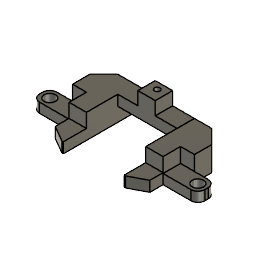
Final Final Assembly (Autodesk Fusion 360 archive; units mm, degrees)
design "Static Arm"
Autodesk Fusion 360 part; units mm, degrees
(part 1 of 3)
sketch "Sketch1" plane through (0, 0, 0) normal (0, 0, 1) x (1, 0, 0)
  line L0 (2.54, 0) -> (57.7596, 0)
  line L1 (60.2996, 2.54) -> (60.2996, 3.81)
  line L2 (57.7596, 6.35) -> (2.54, 6.35)
  line L3 (0, 3.81) -> (0, 2.54)
  circle A0 centre (3.175, 3.175) radius 2.0955
  circle A1 centre (57.1246, 3.175) radius 2.0955
  arc A2 (60.2996, 3.81) -> (57.7596, 6.35) centre (57.7596, 3.81) ccw
  arc A3 (57.7596, 0) -> (60.2996, 2.54) centre (57.7596, 2.54) ccw
  arc A4 (2.54, 6.35) -> (0, 3.81) centre (2.54, 3.81) ccw
  arc A5 (0, 2.54) -> (2.54, 0) centre (2.54, 2.54) ccw
  line L4 (13.335, 17.78) -> (41.275, 17.78)
  line L5 (41.275, 17.78) -> (41.275, 11.43)
  line L6 (41.275, 11.43) -> (13.335, 11.43)
  line L7 (13.335, 11.43) -> (13.335, 17.78)
  line L8 (13.335, 17.78) -> (19.685, 17.78)
  line L9 (19.685, 17.78) -> (19.685, 0)
  line L10 (19.685, 0) -> (13.335, 0)
  line L11 (13.335, 0) -> (13.335, 17.78)
  line L12 (47.5996, 17.78) -> (41.2496, 17.78)
  line L13 (41.2496, 17.78) -> (41.2496, 0)
  line L14 (41.2496, 0) -> (47.5996, 0)
  line L15 (47.5996, 0) -> (47.5996, 17.78)
  line L16 (13.335, 17.78) -> (8.255, 17.78)
  line L17 (8.255, 17.78) -> (8.255, 0)
  line L18 (8.255, 0) -> (13.335, 0)
  line L19 (13.335, 0) -> (13.335, 17.78)
  line L20 (13.335, 17.78) -> (8.255, 12.7)
  line L21 (47.5996, 17.78) -> (52.6796, 17.78)
  line L22 (52.6796, 17.78) -> (52.6796, 0)
  line L23 (52.6796, 0) -> (47.5996, 0)
  line L24 (47.5996, 0) -> (47.5996, 17.78)
  line L25 (47.5996, 17.78) -> (52.6796, 12.7)
  point P0 (60.2996, 0)
  dimension "d1" = 6.35
  dimension "d2" = 60.2996
  dimension "d3" = 4.191
  dimension "d4" = 4.191
  dimension "d5" = 53.9496
  dimension "d6" = 3.175
  dimension "d7" = 3.175
  dimension "d8" = 2.54
  dimension "d9" = 2.54
  dimension "d10" = 2.54
  dimension "d11" = 2.54
  dimension "d14" = 6.35
  dimension "d15" = 10.16
  dimension "d17" = 6.35
  dimension "d18" = 10.16
  dimension "d19" = 5.08
  dimension "d20" = 6.35
  dimension "d39" = 27.94
  dimension "d80" = 5.08
  dimension "d81" = 45
  dimension "d82" = 5.08
  dimension "d83" = 45
  constraint horizontal L0
  constraint vertical L1
  constraint horizontal L2
  constraint vertical L3
  constraint horizontal A0.centre A1.centre
  constraint tangent L2 A2
  constraint tangent L1 A2
  constraint coincident P0 L0
  constraint coincident P0 L1
  constraint tangent L0 A3
  constraint tangent L1 A3
  constraint tangent L3 A4
  constraint tangent L2 A4
  constraint coincident origin L3
  constraint coincident origin L0
  constraint tangent L3 A5
  constraint tangent L0 A5
  constraint horizontal L4
  constraint vertical L5
  constraint horizontal L6
  constraint vertical L7
  constraint horizontal L8
  constraint vertical L9
  constraint horizontal L10
  constraint vertical L11
  constraint coincident L0 L9.end
  constraint horizontal L12
  constraint vertical L13
  constraint horizontal L14
  constraint vertical L15
  constraint coincident L0 L13.end
  constraint coincident L4 L12.start
  constraint horizontal L16
  constraint vertical L17
  constraint horizontal L18
  constraint vertical L19
  constraint coincident L0 L17.end
  constraint coincident L17 L20.end
  constraint horizontal L21
  constraint vertical L22
  constraint horizontal L23
  constraint vertical L24
  constraint coincident L0 L22.end
  constraint coincident L22 L25.end
  measures "d1" distance of L0 L2
  measures "d2" distance of origin P0
  measures "d3" diameter of A0
  measures "d4" diameter of A1
  measures "d5" distance of A0.centre A1.centre
  measures "d6" distance of L3 A0.centre
  measures "d7" vertical distance of origin A0.centre
  measures "d8" radius of A2
  measures "d9" radius of A3
  measures "d10" radius of A4
  measures "d11" radius of A5
  measures "d14" distance of L4 L6
  measures "d15" distance of A0.centre L11
  measures "d17" distance of L13 L15
  measures "d18" distance of A3.centre L15
  measures "d19" distance of L2 L6
  measures "d20" distance of L9 L11
  measures "d39" distance of L4.start L4.end
  measures "d80" distance of L4.start L16.end
  measures "d81" angle of L16 L20
  measures "d82" distance of L12.start L21.end
  measures "d83" angle of L21 L25
extrude "Extrude1" add sketch "Sketch1" along normal blind 3.81 contours L0 L2 L3 A4 A5 L17 | L0 L2 L11 L17 L18 L19 | L0 L2 L9 L10 L11 L19 | L2 L7 L11 L17 L19 L20 | L2 L6 L9 L11 L19 | L0 L2 L13 L14 L15 L24 | L4 L6 L7 L8 L9 L11 L19 | L0 L2 L15 L22 L23 L24 | L2 L5 L6 L12 L13 L15 L24 | L4 L6 L9 L13 | L0 L1 L2 A2 A3 L22 | L2 L15 L22 L24 L25 makes body 1
sketch "Sketch5" plane through (0, 0, 3.81) normal (0, 0, -1) x (1, 0, 0)
  circle A0 centre (63.4746, -3.175) radius 2.0955
  circle A1 centre (3.175, -3.175) radius 2.0955
  line L0 (47.5996, 0) -> (47.5996, -11.43)
  line L1 (47.5996, -11.43) -> (19.335, -11.43)
  line L2 (19.335, -11.43) -> (19.335, 0)
  line L3 (19.335, 0) -> (2.54, 0)
  arc A2 (2.54, 0) -> (0, -2.54) centre (2.54, -2.54) ccw
  line L4 (0, -2.54) -> (0, -3.81)
  arc A3 (0, -3.81) -> (2.54, -6.35) centre (2.54, -3.81) ccw
  line L5 (2.54, -6.35) -> (13.335, -6.35)
  line L6 (13.335, -6.35) -> (13.335, -17.78)
  line L7 (13.335, -17.78) -> (53.9496, -17.78)
  line L8 (53.9496, -17.78) -> (53.9496, -6.35)
  line L9 (53.9496, -6.35) -> (64.1096, -6.35)
  arc A4 (64.1096, -6.35) -> (66.6496, -3.81) centre (64.1096, -3.81) ccw
  line L10 (66.6496, -3.81) -> (66.6496, -2.54)
  arc A5 (66.6496, -2.54) -> (64.1096, 0) centre (64.1096, -2.54) ccw
  line L11 (64.1096, 0) -> (47.5996, 0)
  line L12 (26.9748, -11.43) -> (33.3248, -11.43)
  line L13 (33.3248, -11.43) -> (33.3248, -17.78)
  line L14 (33.3248, -17.78) -> (26.9748, -17.78)
  line L15 (26.9748, -17.78) -> (26.9748, -11.43)
  circle A6 centre (3.175, -3.175) radius 2.0955
  line L16 (8.255, -6.35) -> (2.54, -6.35)
  arc A7 (0, -3.81) -> (2.54, -6.35) centre (2.54, -3.81) ccw
  line L17 (0, -3.81) -> (0, -2.54)
  arc A8 (2.54, 0) -> (0, -2.54) centre (2.54, -2.54) ccw
  line L18 (2.54, 0) -> (19.685, 0)
  line L19 (19.685, 0) -> (19.685, -11.43)
  line L20 (19.685, -11.43) -> (41.2496, -11.43)
  line L21 (41.2496, -11.43) -> (41.2496, -17.78)
  line L22 (41.2496, -17.78) -> (13.335, -17.78)
  line L23 (13.335, -17.78) -> (8.255, -12.7)
  line L24 (8.255, -12.7) -> (8.255, -6.35)
  dimension "d35" = 6.35
  dimension "d36" = 26.9748
  constraint horizontal L12
  constraint vertical L13
  constraint horizontal L14
  constraint vertical L15
  constraint coincident L7 L13.end
  constraint coincident L1 L12.start
  measures "d35" distance of L13 L15
  measures "d36" distance of origin L15
extrude "Extrude4" add sketch "Sketch5" against normal blind 4.8006 contours L1 L7 L12 L13 L14 L15 L20 L22 bodies 1
sketch "Sketch2" plane through (0, 0, 8.6106) normal (0, 0, -1) x (1, 0, 0)
  circle A0 centre (63.4746, -3.175) radius 2.0955
  circle A1 centre (3.175, -3.175) radius 2.0955
  line L0 (47.5996, 0) -> (47.5996, -11.43)
  line L1 (47.5996, -11.43) -> (36.4998, -11.43)
  line L2 (19.335, -11.43) -> (19.335, 0)
  line L3 (19.335, 0) -> (2.54, 0)
  arc A2 (2.54, 0) -> (0, -2.54) centre (2.54, -2.54) ccw
  line L4 (0, -2.54) -> (0, -3.81)
  arc A3 (0, -3.81) -> (2.54, -6.35) centre (2.54, -3.81) ccw
  line L5 (2.54, -6.35) -> (13.335, -6.35)
  line L6 (13.335, -6.35) -> (13.335, -17.78)
  line L7 (36.4998, -17.78) -> (53.9496, -17.78)
  line L8 (53.9496, -17.78) -> (53.9496, -6.35)
  line L9 (53.9496, -6.35) -> (64.1096, -6.35)
  arc A4 (64.1096, -6.35) -> (66.6496, -3.81) centre (64.1096, -3.81) ccw
  line L10 (66.6496, -3.81) -> (66.6496, -2.54)
  arc A5 (66.6496, -2.54) -> (64.1096, 0) centre (64.1096, -2.54) ccw
  line L11 (64.1096, 0) -> (47.5996, 0)
  circle A6 centre (30.1498, -15.3416) radius 1
  line L12 (36.4998, -11.43) -> (36.4998, -17.78)
  line L13 (30.1498, -17.78) -> (30.1498, -11.43)
  line L14 (30.1498, -11.43) -> (19.335, -11.43)
  line L15 (13.335, -17.78) -> (30.1498, -17.78)
  line L16 (30.1498, -17.78) -> (36.4998, -17.78)
  line L17 (36.4998, -17.78) -> (36.4998, -11.43)
  line L18 (36.4998, -11.43) -> (30.1498, -11.43)
  line L19 (30.1498, -11.43) -> (30.1498, -17.78)
  circle A7 centre (63.4746, -3.175) radius 2.0955
  circle A8 centre (3.175, -3.175) radius 2.0955
  line L20 (47.5996, -11.43) -> (47.5996, 0)
  line L21 (2.54, 0) -> (19.335, 0)
  arc A9 (66.6496, -2.54) -> (64.1096, 0) centre (64.1096, -2.54) ccw
  line L22 (66.6496, -2.54) -> (66.6496, -3.81)
  arc A10 (64.1096, -6.35) -> (66.6496, -3.81) centre (64.1096, -3.81) ccw
  line L23 (13.335, -6.35) -> (2.54, -6.35)
  line L24 (53.9496, -6.35) -> (53.9496, -17.78)
  line L25 (30.1498, -17.78) -> (13.335, -17.78)
  line L26 (13.335, -17.78) -> (13.335, -6.35)
  arc A11 (0, -3.81) -> (2.54, -6.35) centre (2.54, -3.81) ccw
  line L27 (0, -3.81) -> (0, -2.54)
  arc A12 (2.54, 0) -> (0, -2.54) centre (2.54, -2.54) ccw
  line L28 (19.335, 0) -> (19.335, -11.43)
  line L29 (19.335, -11.43) -> (30.1498, -11.43)
  line L30 (30.1498, -11.43) -> (30.1498, -17.78)
  line L31 (36.4998, -17.78) -> (36.4998, -11.43)
  line L32 (36.4998, -11.43) -> (47.5996, -11.43)
  line L33 (47.5996, 0) -> (64.1096, 0)
  line L34 (64.1096, -6.35) -> (53.9496, -6.35)
  line L35 (53.9496, -17.78) -> (36.4998, -17.78)
  line L36 (33.3248, -17.78) -> (26.9748, -17.78)
  line L37 (26.9748, -17.78) -> (26.9748, -11.43)
  line L38 (26.9748, -11.43) -> (33.3248, -11.43)
  line L39 (33.3248, -11.43) -> (33.3248, -17.78)
  dimension "d21" = 2
  dimension "d24" = 3.9116
  dimension "d53" = 30.1498
  measures "d21" diameter of A6
  measures "d24" distance of L1 A6.centre
  measures "d53" distance of L4 A6.centre
extrude "Extrude2" cut sketch "Sketch2" along normal blind 12.7 contours A6 L13 L19 L30 | A6 L13 L19 L30 bodies 1
sketch "Sketch3" plane through (0, 0, 3.81) normal (0, 0, 1) x (-1, 0, 0)
  line L0 (-41.2496, 0) -> (-57.7596, 0)
  line L1 (-57.7596, -6.35) -> (-52.6796, -6.35)
  line L2 (-41.275, -11.43) -> (-41.2496, -11.43)
  circle A0 centre (-16.51, -14.605) radius 2.1
  circle A1 centre (-44.4246, -14.605) radius 2.1
  line L3 (-47.5996, -17.78) -> (-41.275, -17.78)
  line L4 (-41.275, -17.78) -> (-41.275, -11.43)
  line L5 (-41.2496, -11.43) -> (-41.2496, 0)
  arc A2 (-57.7596, 0) -> (-60.2996, -2.54) centre (-57.7596, -2.54) ccw
  line L6 (-60.2996, -2.54) -> (-60.2996, -3.81)
  arc A3 (-60.2996, -3.81) -> (-57.7596, -6.35) centre (-57.7596, -3.81) ccw
  circle A4 centre (-57.1246, -3.175) radius 2.0955
  line L7 (-52.6796, -6.35) -> (-52.6796, -12.7)
  line L8 (-52.6796, -12.7) -> (-47.5996, -17.78)
  dimension "d27" = 4.2
  dimension "d28" = 4.2
  dimension "d40" = 14.605
  dimension "d41" = 16.51
  dimension "d42" = 27.9146
  constraint horizontal A0.centre A1.centre
  measures "d27" diameter of A1
  measures "d28" diameter of A0
  measures "d40" vertical distance of origin A0.centre
  measures "d41" horizontal distance of origin A0.centre
  measures "d42" distance of A0.centre A1.centre
sketch "Sketch6" plane through (0, 0, 0) normal (0, 0, -1) x (1, 0, 0)
  circle A0 centre (57.1246, -3.175) radius 2.0955
  line L0 (52.6796, -6.35) -> (57.7596, -6.35)
  arc A1 (57.7596, -6.35) -> (60.2996, -3.81) centre (57.7596, -3.81) ccw
  line L1 (60.2996, -3.81) -> (60.2996, -2.54)
  arc A2 (60.2996, -2.54) -> (57.7596, 0) centre (57.7596, -2.54) ccw
  line L2 (57.7596, 0) -> (41.2496, 0)
  line L3 (41.2496, 0) -> (41.2496, -11.43)
  line L4 (41.2496, -11.43) -> (41.275, -11.43)
  line L5 (41.275, -11.43) -> (41.275, -17.78)
  line L6 (41.275, -17.78) -> (47.5996, -17.78)
  line L7 (41.2496, 0) -> (47.5996, 0)
  line L8 (47.5996, 0) -> (47.5996, -17.78)
  line L9 (47.5996, -17.78) -> (41.2496, -17.78)
  line L10 (41.2496, -17.78) -> (41.2496, 0)
  line L11 (47.5996, 0) -> (57.7596, 0)
  line L12 (60.2996, -2.54) -> (60.2996, -3.81)
  line L13 (57.7596, -6.35) -> (47.5996, -6.35)
  line L14 (47.5996, -6.35) -> (47.5996, 0)
  arc A3 (60.2996, -2.54) -> (57.7596, 0) centre (57.7596, -2.54) ccw
  arc A4 (57.7596, -6.35) -> (60.2996, -3.81) centre (57.7596, -3.81) ccw
  line L15 (19.685, -17.78) -> (13.335, -17.78)
  line L16 (13.335, -17.78) -> (13.335, 0)
  line L17 (13.335, 0) -> (19.685, 0)
  line L18 (19.685, 0) -> (19.685, -17.78)
  line L19 (13.335, 0) -> (2.54, 0)
  line L20 (0, -2.54) -> (0, -3.81)
  line L21 (2.54, -6.35) -> (13.335, -6.35)
  line L22 (13.335, -6.35) -> (13.335, 0)
  arc A5 (2.54, 0) -> (0, -2.54) centre (2.54, -2.54) ccw
  arc A6 (0, -3.81) -> (2.54, -6.35) centre (2.54, -3.81) ccw
  circle A7 centre (3.175, -3.175) radius 2.0955
  circle A8 centre (16.51, -14.5999) radius 2.0955
  line L23 (47.5996, -17.78) -> (52.6796, -12.7)
  line L24 (52.6796, -12.7) -> (52.6796, -6.35)
  point P0 (19.685, 0)
  point P1 (0, -2.54)
  point P2 (41.2496, -17.78)
  point P3 (13.335, -17.78)
  dimension "d43" = 2.54
  dimension "d44" = 2.54
  dimension "d45" = 10.16
  dimension "d46" = 1.27
  dimension "d54" = 6.35
  dimension "d55" = 2.54
  dimension "d56" = 2.54
  dimension "d57" = 6.35
  dimension "d58" = 3.175
  dimension "d59" = 4.191
  dimension "d60" = 3.175
  dimension "d61" = 4.191
  dimension "d62" = 3.1801
  dimension "d63" = 3.175
  constraint horizontal L7
  constraint vertical L8
  constraint horizontal L9
  constraint vertical L10
  constraint coincident L6.end L8.end
  constraint coincident L2.end L3.start
  constraint horizontal L11
  constraint vertical L12
  constraint horizontal L13
  constraint vertical L14
  constraint tangent L11 A3
  constraint tangent L12 A3
  constraint tangent L12 A4
  constraint tangent L13 A4
  constraint horizontal L15
  constraint vertical L16
  constraint horizontal L17
  constraint vertical L18
  constraint coincident P0 L17.end
  constraint horizontal L19
  constraint vertical L20
  constraint horizontal L21
  constraint vertical L22
  constraint tangent L20 A5
  constraint tangent L19 A5
  constraint tangent L20 A6
  constraint tangent L21 A6
  constraint coincident P1 L20.start
  measures "d43" radius of A3
  measures "d44" radius of A4
  measures "d45" distance of L13.end L0.end
  measures "d46" distance of L1.end A1.end
  measures "d54" distance of L16 L18
  measures "d55" radius of A5
  measures "d56" radius of A6
  measures "d57" distance of L19 L21
  measures "d58" distance of L19 A7.centre
  measures "d59" diameter of A7
  measures "d60" distance of L20 A7.centre
  measures "d61" diameter of A8
  measures "d62" distance of L15 A8.centre
  measures "d63" distance of L16 A8.centre
extrude "Extrude6" cut sketch "Sketch6" against normal blind 7.62 contours L0 A1 L1 A2 L2 L8 L11 L12 L13 L14 A3 A4 | L16 L19 L20 L21 L22 A5 A6 bodies 1
extrude "Extrude5" add sketch "Sketch6" along normal blind 5.08 separate body contours L0 A1 L1 A2 L2 L8 L11 L12 L13 L14 A3 A4 | L2 L3 L4 L5 L6 L7 L8 L9 L10 L14 | L15 L16 L17 L18 L22 | L16 L19 L20 L21 L22 A5 A6 | A8 makes body 2 at (43.3747, 5.9267, 0) makes body 3 at (17.5683, 8.0433, 0)
extrude "Extrude7" cut sketch "Sketch6" along normal blind 1.27 contours L0 A1 L1 A2 L2 L8 L11 L12 L13 L14 A3 A4 | L16 L19 L20 L21 L22 A5 A6 bodies 2
extrude "Extrude8" cut sketch "Sketch6" along normal blind 1.27 contours L16 L19 L20 L21 L22 A5 A6 bodies 3
sketch "Sketch7" plane through (0, 0, 0) normal (0, -1, 0) x (1, 0, 0)
  line L0 (13.335, -1.27) -> (2.54, -1.27)
  line L1 (2.54, -1.27) -> (2.54, -5.08)
  line L2 (2.54, -5.08) -> (19.685, -5.08)
  line L3 (19.685, -5.08) -> (19.685, 0)
  line L4 (19.685, 0) -> (13.335, 0)
  line L5 (13.335, 0) -> (13.335, -1.27)
  line L6 (13.335, -1.27) -> (19.685, -1.27)
  line L7 (19.685, -1.27) -> (19.685, -5.08)
  line L8 (19.685, -5.08) -> (13.335, -5.08)
  line L9 (13.335, -5.08) -> (13.335, -1.27)
  dimension "d66" = 6.35
  constraint horizontal L6
  constraint vertical L7
  constraint horizontal L8
  constraint vertical L9
  constraint coincident L2 L3.start
  constraint coincident L0 L5.end
  constraint coincident L2.end L3.start
  measures "d66" distance of L7 L9
extrude "Extrude9" add sketch "Sketch7" along normal blind 8.4226 contours L2 L3 L6 L7 L8 L9 bodies 3
chamfer "Chamfer1" distance 5.842 angle 30.099 1 edges at (13.335, -8.4226, -3.175) measured on face at (15.4517, -8.4226, -3.81) on bodies 3
sketch "Sketch8" plane through (0, 0, 0) normal (0, -1, 0) x (1, 0, 0)
  line L0 (57.7596, -1.27) -> (47.5996, -1.27)
  line L1 (47.5996, -1.27) -> (47.5996, 0)
  line L2 (47.5996, 0) -> (41.2496, 0)
  line L3 (41.2496, 0) -> (41.2496, -5.08)
  line L4 (41.2496, -5.08) -> (57.7596, -5.08)
  line L5 (57.7596, -5.08) -> (57.7596, -1.27)
  line L6 (41.2496, -5.08) -> (47.5996, -5.08)
  line L7 (47.5996, -5.08) -> (47.5996, -1.27)
  line L8 (47.5996, -1.27) -> (41.2496, -1.27)
  line L9 (41.2496, -1.27) -> (41.2496, -5.08)
  constraint horizontal L6
  constraint vertical L7
  constraint horizontal L8
  constraint vertical L9
  constraint coincident L0.end L1.start
  constraint coincident L3.end L4.start
extrude "Extrude10" add sketch "Sketch8" along normal blind 7.874 contours L3 L4 L6 L7 L8 L9 bodies 2
chamfer "Chamfer2" distance 5.842 angle 27.549 1 edges at (47.5996, -7.874, -3.175) measured on face at (45.4829, -7.874, -3.81) on bodies 2
sketch "Sketch9" plane through (0, 0, 0) normal (0, 0, -1) x (1, 0, 0)
  line L0 (47.5996, -6.35) -> (47.5996, 0)
  line L1 (47.5996, 0) -> (41.2496, 0)
  line L2 (41.2496, 0) -> (41.2496, -11.43)
  line L3 (41.2496, -11.43) -> (41.275, -11.43)
  line L4 (41.275, -11.43) -> (41.275, -17.78)
  line L5 (41.275, -17.78) -> (47.5996, -17.78)
  line L6 (47.5996, -17.78) -> (52.6796, -12.7)
  line L7 (52.6796, -12.7) -> (52.6796, -6.35)
  line L8 (52.6796, -6.35) -> (47.5996, -6.35)
  line L9 (47.5996, -6.35) -> (52.6796, -6.35)
  line L10 (52.6796, -6.35) -> (52.6796, -12.7)
  line L11 (52.6796, -12.7) -> (47.5996, -12.7)
  line L12 (47.5996, -12.7) -> (47.5996, -6.35)
  line L13 (47.5996, -12.7) -> (47.5996, -17.78)
  line L14 (52.6796, -12.7) -> (47.5996, -17.78)
  constraint horizontal L9
  constraint vertical L10
  constraint horizontal L11
  constraint vertical L12
  constraint coincident L6.end L7.start
  constraint coincident L0.start L8.end
  constraint coincident L5.end L6.start
extrude "Extrude11" add sketch "Sketch9" along normal blind 5.08 contours L7 L8 L9 L10 L11 L12 | L6 L11 L13 L14 bodies 1 3 2
sketch "Sketch10" plane through (0, 0, 0) normal (0, 0, -1) x (1, 0, 0)
  line L0 (13.335, 0) -> (13.335, -6.35)
  line L1 (13.335, -6.35) -> (8.255, -6.35)
  line L2 (8.255, -6.35) -> (8.255, -12.7)
  line L3 (8.255, -12.7) -> (13.335, -17.78)
  line L4 (13.335, -17.78) -> (41.2496, -17.78)
  line L5 (41.2496, -17.78) -> (41.2496, -11.43)
  line L6 (41.2496, -11.43) -> (19.685, -11.43)
  line L7 (19.685, -11.43) -> (19.685, 0)
  line L8 (19.685, 0) -> (13.335, 0)
  circle A0 centre (30.1498, -15.3416) radius 1
  line L9 (8.255, -6.35) -> (13.335, -6.35)
  line L10 (13.335, -6.35) -> (13.335, -12.7)
  line L11 (13.335, -12.7) -> (8.255, -12.7)
  line L12 (8.255, -12.7) -> (8.255, -6.35)
  line L13 (13.335, -12.7) -> (13.335, -17.78)
  line L14 (8.255, -12.7) -> (13.335, -17.78)
  dimension "d86" = 5.08
  constraint horizontal L9
  constraint vertical L10
  constraint horizontal L11
  constraint vertical L12
  constraint coincident L1.end L2.start
  constraint coincident L2.end L3.start
  constraint coincident L3.end L4.start
  measures "d86" distance of L10.end L2.end
extrude "Extrude12" add sketch "Sketch10" along normal blind 5.08 contours L1 L2 L9 L10 L11 L12 | L3 L11 L13 L14 bodies 1 3
sketch "Sketch11" plane through (0, 0, -1.27) normal (0, 0, 1) x (-1, 0, 0)
  circle A0 centre (-3.175, -3.175) radius 2.0955
  arc A1 (-2.54, -6.35) -> (0, -3.81) centre (-2.54, -3.81) ccw
  line L0 (0, -3.81) -> (0, -2.54)
  arc A2 (0, -2.54) -> (-2.54, 0) centre (-2.54, -2.54) ccw
  line L1 (-2.54, 0) -> (-13.335, 0)
  line L2 (-13.335, 0) -> (-13.335, -6.35)
  line L3 (-13.335, -6.35) -> (-8.255, -6.35)
  line L4 (-8.255, -6.35) -> (-2.54, -6.35)
  line L5 (-13.335, -6.35) -> (5.715, -6.35)
  line L6 (5.715, -6.35) -> (5.715, 6.35)
  line L7 (5.715, 6.35) -> (-13.335, 6.35)
  line L8 (-13.335, 6.35) -> (-13.335, -6.35)
  line L9 (-47.5996, -6.35) -> (-66.6496, -6.35)
  line L10 (-66.6496, -6.35) -> (-66.6496, 6.35)
  line L11 (-66.6496, 6.35) -> (-47.5996, 6.35)
  line L12 (-47.5996, 6.35) -> (-47.5996, -6.35)
  point P0 (-47.5996, -6.35)
  dimension "d89" = 12.7
  dimension "d90" = 19.05
  dimension "d91" = 12.7
  dimension "d92" = 19.05
  constraint horizontal L5
  constraint vertical L6
  constraint horizontal L7
  constraint vertical L8
  constraint coincident L2.end L3.start
  constraint horizontal L9
  constraint vertical L10
  constraint horizontal L11
  constraint vertical L12
  constraint coincident P0 L9.start
  measures "d89" distance of L9.end L10.end
  measures "d90" distance of P0 L9.end
  measures "d91" distance of L5.end L6.end
  measures "d92" distance of L2.end L5.end
extrude "Extrude13" cut sketch "Sketch11" against normal blind 0.254 bodies 1
fillet "Fillet1" [rolled back] radius 10.16
fillet "Fillet2" [rolled back] radius 10.16
equation "d5 = 2.374 in - 0.25 in"
equation "d36 = ( 2.624 / 2 ) * 1 in - 0.25 in"
equation "d42 = 1.349 in - 0.25 in"
equation "d53 = ( 2.374 / 2 ) * 1 in"

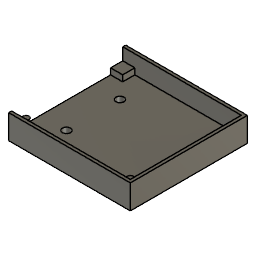
design "Controller Mounting"
Autodesk Fusion 360 part; units mm, degrees
sketch "Sketch1" plane through (0, 0, 0) normal (0, 0, 1) x (1, 0, 0)
  line L0 (0, 0) -> (65.175, 0)
  line L1 (65.175, 0) -> (65.175, 61.175)
  line L2 (65.175, 61.175) -> (0, 61.175)
  line L3 (0, 61.175) -> (0, 0)
  dimension "d1" = 61.175
  dimension "d2" = 65.175
  constraint horizontal L0
  constraint vertical L1
  constraint horizontal L2
  constraint vertical L3
  constraint coincident L0.start L3.end
  measures "d1" distance of L0.start L2.end
  measures "d2" distance of L0.start L0.end
extrude "Extrude1" add sketch "Sketch1" along normal blind 12.7
sketch "Sketch4" plane through (0, 0, 12.7) normal (0, 0, 1) x (-1, 0, 0)
  line L0 (0, -61.175) -> (0, 0)
  line L1 (0, 0) -> (-65.175, 0)
  line L2 (-65.175, 0) -> (-65.175, -61.175)
  line L3 (-65.175, -61.175) -> (0, -61.175)
  line L4 (-1.5875, -1.5875) -> (-63.5875, -1.5875)
  line L5 (-63.5875, -1.5875) -> (-63.5875, -59.5875)
  line L6 (-63.5875, -59.5875) -> (-1.5875, -59.5875)
  line L7 (-1.5875, -59.5875) -> (-1.5875, -1.5875)
  dimension "d10" = 1.5875
  dimension "d11" = 1.5875
  dimension "d12" = 1.5875
  dimension "d13" = 1.5875
  constraint horizontal L4
  constraint vertical L5
  constraint horizontal L6
  constraint vertical L7
  measures "d10" distance of L0 L7
  measures "d11" distance of L3 L6
  measures "d12" distance of L1 L4
  measures "d13" distance of L2 L5
extrude "Extrude2" cut sketch "Sketch4" against normal blind 9.525 contours L4 L5 L6 L7
sketch "Sketch5" plane through (0, 0, 0) normal (-1, 0, 0) x (0, -1, 0)
  line L0 (-61.175, 0) -> (0, 0)
  line L1 (0, 0) -> (0, 12.7)
  line L2 (0, 12.7) -> (-61.175, 12.7)
  line L3 (-61.175, 12.7) -> (-61.175, 0)
  line L4 (-53.2375, 12.7) -> (-7.9375, 12.7)
  line L5 (-7.9375, 12.7) -> (-7.9375, 0)
  line L6 (-53.2375, 0) -> (-53.2375, 12.7)
  line L7 (-53.2375, 3.175) -> (-59.5875, 3.175)
  line L8 (-59.5875, 3.175) -> (-59.5875, 12.7)
  line L9 (-59.5875, 12.7) -> (-53.2375, 12.7)
  line L10 (-53.2375, 12.7) -> (-53.2375, 3.175)
  line L11 (-7.9375, 3.175) -> (-1.5875, 3.175)
  line L12 (-1.5875, 3.175) -> (-1.5875, 12.7)
  line L13 (-1.5875, 12.7) -> (-7.9375, 12.7)
  line L14 (-7.9375, 12.7) -> (-7.9375, 3.175)
  line L15 (-53.2375, 3.175) -> (-7.9375, 3.175)
  dimension "d76" = 1.5875
  dimension "d77" = 3.175
  dimension "d78" = 3.175
  dimension "d79" = 1.5875
  dimension "d80" = 6.35
  dimension "d81" = 6.35
  constraint horizontal L4
  constraint vertical L5
  constraint vertical L6
  constraint coincident L2 L4.start
  constraint horizontal L5.end L6.start
  constraint horizontal L0.end L6.start
  constraint horizontal L7
  constraint vertical L8
  constraint horizontal L9
  constraint vertical L10
  constraint coincident L2 L8.end
  constraint coincident L6 L7.start
  constraint horizontal L11
  constraint vertical L12
  constraint horizontal L13
  constraint vertical L14
  constraint coincident L2 L12.end
  constraint coincident L5 L11.start
  measures "d76" distance of L3 L8
  measures "d77" distance of L0 L7
  measures "d78" distance of L0 L11
  measures "d79" distance of L1 L12
  measures "d80" distance of L8 L10
  measures "d81" distance of L12 L14
extrude "Extrude3" cut sketch "Sketch5" against normal blind 1.5875
sketch "Sketch6" plane through (0, 0, 3.175) normal (0, 0, 1) x (-1, 0, 0)
  circle A0 centre (-59.8375, -5.3375) radius 1.65
  circle A1 centre (-5.3375, -5.3375) radius 1.65
  circle A2 centre (-59.8375, -55.8375) radius 1.65
  circle A3 centre (-5.3375, -55.8375) radius 1.65
  line L0 (-63.5875, -1.5875) -> (-57.2375, -1.5875)
  line L1 (-57.2375, -1.5875) -> (-57.2375, -7.9375)
  line L2 (-57.2375, -7.9375) -> (-63.5875, -7.9375)
  line L3 (-63.5875, -7.9375) -> (-63.5875, -1.5875)
  line L4 (-63.5875, -59.5875) -> (-57.2375, -59.5875)
  line L5 (-57.2375, -59.5875) -> (-57.2375, -53.2375)
  line L6 (-57.2375, -53.2375) -> (-63.5875, -53.2375)
  line L7 (-63.5875, -53.2375) -> (-63.5875, -59.5875)
  line L8 (-1.5875, -59.5875) -> (-7.9375, -59.5875)
  line L9 (-7.9375, -59.5875) -> (-7.9375, -53.2375)
  line L10 (-7.9375, -53.2375) -> (-1.5875, -53.2375)
  line L11 (-1.5875, -53.2375) -> (-1.5875, -59.5875)
  line L12 (-1.5875, -1.5875) -> (-7.9375, -1.5875)
  line L13 (-7.9375, -1.5875) -> (-7.9375, -7.9375)
  line L14 (-7.9375, -7.9375) -> (-1.5875, -7.9375)
  line L15 (-1.5875, -7.9375) -> (-1.5875, -1.5875)
  line L16 (-65.175, 0) -> (-65.175, -61.175)
  line L17 (-65.175, -61.175) -> (0, -61.175)
  line L18 (-1.5875, -1.5875) -> (-63.5875, -1.5875)
  line L19 (-63.5875, -1.5875) -> (-63.5875, -59.5875)
  line L20 (-63.5875, -59.5875) -> (-1.5875, -59.5875)
  line L21 (-1.5875, -59.5875) -> (-1.5875, -1.5875)
  dimension "d82" = 3.3
  dimension "d83" = 50.5
  dimension "d84" = 50.5
  dimension "d85" = 54.5
  dimension "d86" = 3.3
  dimension "d87" = 3.3
  dimension "d88" = 5.3375
  dimension "d89" = 5.3375
  dimension "d90" = 6.35
  dimension "d91" = 6.35
  dimension "d92" = 6.35
  dimension "d93" = 6.35
  dimension "d94" = 6.35
  dimension "d95" = 6.35
  dimension "d96" = 6.35
  dimension "d97" = 6.35
  dimension "d98" = 1.5875
  dimension "d100" = 1.5875
  dimension "d101" = 1.5875
  dimension "d102" = 1.5875
  constraint horizontal A0.centre A1.centre
  constraint horizontal A2.centre A3.centre
  constraint vertical A1.centre A3.centre
  constraint equal A0 A1
  constraint horizontal L0
  constraint vertical L1
  constraint horizontal L2
  constraint vertical L3
  constraint horizontal L4
  constraint vertical L5
  constraint horizontal L6
  constraint vertical L7
  constraint horizontal L8
  constraint vertical L9
  constraint horizontal L10
  constraint vertical L11
  constraint horizontal L12
  constraint vertical L13
  constraint horizontal L14
  constraint vertical L15
  constraint horizontal L1.end L13.end
  constraint vertical L9.end L13.end
  constraint horizontal L5.end L9.end
  constraint vertical L1.end L5.end
  measures "d82" diameter of A0
  measures "d83" distance of A0.centre A2.centre
  measures "d84" vertical distance of A1.centre A3.centre
  measures "d85" distance of A0.centre A1.centre
  measures "d86" diameter of A2
  measures "d87" diameter of A3
  measures "d88" vertical distance of origin A0.centre
  measures "d89" horizontal distance of origin A1.centre
  measures "d90" distance of L12.end L13.end
  measures "d91" distance of L13.end L14.end
  measures "d92" distance of L9.end L10.end
  measures "d93" distance of L8.end L9.end
  measures "d94" distance of L4.end L5.end
  measures "d95" distance of L5.end L6.end
  measures "d96" distance of L1.end L2.end
  measures "d97" distance of L0.end L1.end
  measures "d98" distance of origin L12
  measures "d100" distance of origin L15
  measures "d101" distance of L3 L16
  measures "d102" distance of L4 L17
extrude "Extrude4" add sketch "Sketch6" along normal blind 3.175 contours A0 | A1 | A2 | A3 | L0 L1 L2 L3 L18 L19 | L12 L13 L14 L15 L18 L21 | L4 L5 L6 L7 L19 L20 | L8 L9 L10 L11 L20 L21
extrude "Extrude8" add sketch "Sketch6" along normal blind 6.35 contours A0 | A1
sketch "Sketch7" plane through (0, 0, 3.175) normal (0, 0, 1) x (-1, 0, 0)
  line L0 (-7.9375, -1.5875) -> (-57.2375, -1.5875)
  circle A0 centre (-15.2005, -16.6175) radius 2.1
  circle A1 centre (-15.2005, -44.5575) radius 2.1
  line L1 (-1.5875, 0) -> (-65.175, 0)
  line L2 (-15.2005, -16.6175) -> (-15.2005, -44.5575)
  line L3 (-15.2005, 0) -> (-15.2005, -61.175)
  line L4 (-65.175, -61.175) -> (-1.5875, -61.175)
  line L5 (-57.2375, -59.5875) -> (-7.9375, -59.5875)
  line L6 (-63.5875, -7.9375) -> (-63.5875, -53.2375)
  line L7 (-63.5875, -53.2375) -> (-57.2375, -53.2375)
  line L8 (-57.2375, -53.2375) -> (-57.2375, -59.5875)
  line L9 (-7.9375, -59.5875) -> (-7.9375, -53.2375)
  line L10 (-7.9375, -53.2375) -> (-1.5875, -53.2375)
  line L11 (-1.5875, -53.2375) -> (-1.5875, -7.9375)
  line L12 (-1.5875, -7.9375) -> (-7.9375, -7.9375)
  line L13 (-7.9375, -7.9375) -> (-7.9375, -1.5875)
  line L14 (-57.2375, -1.5875) -> (-57.2375, -7.9375)
  line L15 (-57.2375, -7.9375) -> (-63.5875, -7.9375)
  dimension "d41" = 4.2
  dimension "d42" = 4.2
  dimension "d43" = 27.94
  dimension "d108" = 13.613
  constraint vertical A0.centre A1.centre
  constraint coincident A0.centre L2.start
  constraint coincident A1.centre L2.end
  constraint coincident L1 L3.start
  constraint midpoint L2 L3
  constraint coincident L3.end L4
  constraint vertical L3.start L3.end
  measures "d41" diameter of A1
  measures "d42" diameter of A0
  measures "d43" distance of A0.centre A1.centre
  measures "d108" distance of L2 L11
extrude "Extrude5" cut sketch "Sketch7" against normal blind 3.175 contours A0 L2 L3 | A0 L2 L3 | A1 L2 L3 | A1 L2 L3
sketch "Sketch9" plane through (0, 0, 0) normal (0, 0, -1) x (1, 0, 0)
  line L0 (1.5875, -61.175) -> (65.175, -61.175)
  line L1 (65.175, -61.175) -> (65.175, 0)
  line L2 (65.175, 0) -> (1.5875, 0)
  circle A0 centre (19.0373, -54.4) radius 1.6
  circle A1 centre (44.4373, -54.4) radius 1.6
  circle A2 centre (19.0373, -6.775) radius 1.6
  circle A3 centre (44.4373, -6.775) radius 1.6
  circle A4 centre (15.2005, -16.6175) radius 2.1
  circle A5 centre (15.2005, -44.5575) radius 2.1
  line L3 (44.4373, -6.775) -> (44.4373, 0)
  line L4 (44.4373, -54.4) -> (44.4373, -61.175)
  line L5 (1.5875, 0) -> (1.5875, -61.175)
  dimension "d60" = 3.2
  dimension "d61" = 3.2
  dimension "d75" = 25.4
  dimension "d105" = 47.625
  dimension "d106" = 47.625
  constraint vertical A0.centre A2.centre
  constraint vertical A1.centre A3.centre
  constraint equal A0 A2
  constraint equal A0 A3
  constraint horizontal A2.centre A3.centre
  constraint coincident A3.centre L3.start
  constraint coincident L2 L3.end
  constraint perpendicular L2 L3
  constraint coincident A1.centre L4.start
  constraint coincident L0 L4.end
  constraint perpendicular L0 L4
  constraint equal L3 L4
  measures "d60" diameter of A0
  measures "d61" diameter of A1
  measures "d75" distance of A0.centre A1.centre
  measures "d105" distance of A1.centre A3.centre
  measures "d106" distance of A0.centre A2.centre
equation "d1 = 58 mm + 0.125 in"
equation "d2 = 62 mm + 0.125 in"
equation "d10 = ( 1 / 16 ) * 1 in"
equation "d11 = ( 1 / 16 ) * 1 in"
equation "d12 = ( 1 / 16 ) * 1 in"
equation "d13 = ( 1 / 16 ) * 1 in"
equation "d14 = -0.5 in + 0.125 in"
equation "d20 = ( -1 / 16 ) * 1 in"
equation "d76 = ( 1 / 16 ) * 1 in"
equation "d79 = ( 1 / 16 ) * 1 in"
equation "d88 = ( 1 / 16 ) * 1 in + 3.75 mm"
equation "d89 = ( 1 / 16 ) * 1 in + 3.75 mm"
equation "d98 = ( 1 / 16 ) * 1 in"
equation "d100 = ( 1 / 16 ) * 1 in"
equation "d101 = ( 1 / 16 ) * 1 in"
equation "d102 = ( 1 / 16 ) * 1 in"
equation "d57 = 1.8 in + 0.388 in"
equation "d58 = 0.5 in - 0.052 in - 0.0865 in + 0.388 in"
equation "d71 = 0.101 in + ( 0.173 / 2 ) * 1 in"
equation "d72 = 0.101 in + ( 0.173 / 2 ) * 1 in"

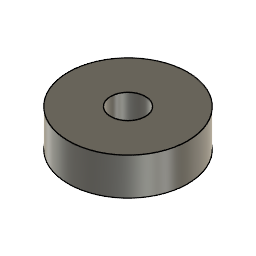
design "Front Wheel"
Autodesk Fusion 360 part; units mm, degrees
sketch "Sketch1" plane through (0, 0, 0) normal (0, 0, 1) x (1, 0, 0)
  circle A0 centre (0, 0) radius 15.24
  circle A1 centre (0, 0) radius 4.445
  dimension "d1" = 8.89
  dimension "d2" = 30.48
  constraint coincident A0.centre A1.centre
  measures "d1" diameter of A1
  measures "d2" diameter of A0
extrude "Extrude1" add sketch "Sketch1" along normal blind 9.525
equation "d3 = ( 3 / 8 ) * 1 in"

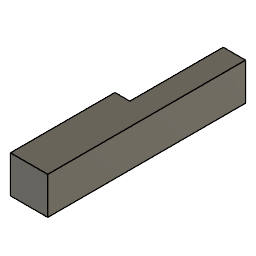
design "Left Fake Cross Base Beam"
Autodesk Fusion 360 part; units mm, degrees
sketch "Sketch1" plane through (0, 0, 0) normal (1, 0, 0) x (0, 1, 0)
  circle A0 centre (0, 0) radius 2.1971
  circle A1 centre (25.4, 0) radius 2.1971
  line L0 (10.16, 2.54) -> (15.24, 2.54)
  line L1 (15.24, 2.54) -> (15.24, -2.54)
  line L2 (15.24, -2.54) -> (10.16, -2.54)
  line L3 (10.16, -2.54) -> (10.16, 2.54)
  line L4 (-6.35, 4.7625) -> (31.75, 4.7625)
  line L5 (31.75, 4.7625) -> (31.75, -4.7625)
  line L6 (31.75, -4.7625) -> (-6.35, -4.7625)
  line L7 (-6.35, -4.7625) -> (-6.35, 4.7625)
  dimension "d1" = 25.4
  dimension "d2" = 4.3942
  dimension "d3" = 4.3942
  dimension "d4" = 5.08
  dimension "d5" = 5.08
  dimension "d6" = 2.54
  dimension "d7" = 10.16
  dimension "d8" = 9.525
  dimension "d9" = 38.1
  dimension "d10" = 4.7625
  dimension "d11" = 6.35
  constraint horizontal A0.centre A1.centre
  constraint horizontal L0
  constraint vertical L1
  constraint horizontal L2
  constraint vertical L3
  constraint coincident A0.centre origin
  constraint horizontal L4
  constraint vertical L5
  constraint horizontal L6
  constraint vertical L7
  measures "d1" distance of A0.centre A1.centre
  measures "d2" diameter of A0
  measures "d3" diameter of A1
  measures "d4" distance of L0.start L0.end
  measures "d5" distance of L0.start L2.end
  measures "d6" distance of A0.centre L0
  measures "d7" horizontal distance of A0.centre L2.end
  measures "d8" distance of L4.start L6.end
  measures "d9" distance of L4.start L4.end
  measures "d10" distance of A0.centre L4
  measures "d11" distance of A0.centre L7
extrude "Extrude1" add sketch "Sketch1" along normal blind 2.54 contours A0 | A1 | L0 L1 L2 L3 | L4 L5 L6 L7
sketch "Sketch2" plane through (2.54, 0, 0) normal (1, 0, 0) x (0, 1, 0)
  line L0 (-6.35, -4.7625) -> (31.75, -4.7625)
  line L1 (31.75, -4.7625) -> (31.75, 4.7625)
  line L2 (31.75, 4.7625) -> (-6.35, 4.7625)
  line L3 (-6.35, 4.7625) -> (-6.35, -4.7625)
  line L4 (31.75, 4.7625) -> (-6.35, 4.7625)
  line L5 (-6.35, 4.7625) -> (-6.35, -4.7625)
  line L6 (-6.35, -4.7625) -> (31.75, -4.7625)
  line L7 (31.75, -4.7625) -> (31.75, 4.7625)
  circle A0 centre (0, 0) radius 2.1971
  circle A1 centre (25.4, 0) radius 2.1971
  dimension "d14" = 4.3942
  dimension "d15" = 4.3942
  constraint horizontal L4
  constraint vertical L5
  constraint horizontal L6
  constraint vertical L7
  constraint coincident L0.start L3.end
  constraint coincident L1.end L2.start
  measures "d14" diameter of A0
  measures "d15" diameter of A1
extrude "Extrude2" add sketch "Sketch2" along normal blind 3.81 contours L0 L1 L2 L3 L4 L5 L6 L7 | A0 | A1
sketch "Sketch3" plane through (0, -6.35, 0) normal (0, -1, 0) x (1, 0, 0)
  line L0 (0, 4.7625) -> (0, -4.7625)
  line L1 (0, -4.7625) -> (6.35, -4.7625)
  line L2 (6.35, -4.7625) -> (6.35, 4.7625)
  line L3 (6.35, 4.7625) -> (0, 4.7625)
  line L4 (0, 4.7625) -> (6.35, 4.7625)
  line L5 (6.35, 4.7625) -> (6.35, -4.7625)
  line L6 (6.35, -4.7625) -> (0, -4.7625)
  line L7 (0, -4.7625) -> (0, 4.7625)
  constraint horizontal L4
  constraint vertical L5
  constraint horizontal L6
  constraint vertical L7
  constraint coincident L1.end L2.start
  constraint coincident L0.start L3.end
extrude "Extrude3" add sketch "Sketch3" along normal blind 127
sketch "Sketch4" plane through (6.35, 0, 0) normal (1, 0, 0) x (0, 1, 0)
  line L0 (31.75, -4.7625) -> (31.75, 4.7625)
  line L1 (31.75, 4.7625) -> (-133.35, 4.7625)
  line L2 (-133.35, 4.7625) -> (-133.35, -4.7625)
  line L3 (-133.35, -4.7625) -> (31.75, -4.7625)
  circle A0 centre (-47.625, 1.5875) radius 1.6
  circle A1 centre (-22.225, 1.5875) radius 1.6
  dimension "d22" = 3.2
  dimension "d23" = 3.2
  dimension "d27" = 6.35
  dimension "d62" = 25.4
  constraint horizontal A0.centre A1.centre
  measures "d22" diameter of A0
  measures "d23" diameter of A1
  measures "d27" distance of L3 A1.centre
  measures "d62" distance of A0.centre A1.centre
sketch "Sketch6" plane through (0, -133.35, 0) normal (0, -1, 0) x (1, 0, 0)
  line L0 (0, -4.7625) -> (6.35, -4.7625)
  line L1 (6.35, -4.7625) -> (6.35, 4.7625)
  line L2 (6.35, 4.7625) -> (0, 4.7625)
  line L3 (0, 4.7625) -> (0, -4.7625)
  line L4 (0, 4.7625) -> (6.35, 4.7625)
  line L5 (6.35, 4.7625) -> (6.35, -1.5875)
  line L6 (6.35, -1.5875) -> (0, -1.5875)
  line L7 (0, -1.5875) -> (0, 4.7625)
  dimension "d29" = 6.35
  dimension "d30" = 6.35
  constraint horizontal L4
  constraint vertical L5
  constraint horizontal L6
  constraint vertical L7
  constraint coincident L2.end L3.start
  measures "d29" distance of L2.end L1.end
  measures "d30" distance of L2.end L6.end
extrude "Extrude5" cut sketch "Sketch6" against normal blind 67.945 contours L0 L1 L3 L6
sketch "Sketch7" plane through (0, 0, 0) normal (-1, 0, 0) x (0, -1, 0)
  line L0 (65.405, -4.7625) -> (65.405, -1.5875)
  line L1 (65.405, -1.5875) -> (133.35, -1.5875)
  line L2 (133.35, -1.5875) -> (133.35, 4.7625)
  line L3 (133.35, 4.7625) -> (-31.75, 4.7625)
  line L4 (-31.75, 4.7625) -> (-31.75, -4.7625)
  line L5 (-31.75, -4.7625) -> (65.405, -4.7625)
  circle A0 centre (117.475, 1.5875) radius 2.1
  dimension "d33" = 4.2
  dimension "d34" = 3.175
  dimension "d35" = 15.875
  measures "d33" diameter of A0
  measures "d34" distance of L3 A0.centre
  measures "d35" distance of L2 A0.centre
extrude "Extrude6" cut sketch "Sketch7" against normal blind 6.35 contours A0
sketch "Sketch8" plane through (0, 0, 0) normal (-1, 0, 0) x (0, -1, 0)
  circle A0 centre (117.475, 1.5875) radius 2.1
  line L0 (65.405, -4.7625) -> (65.405, -1.5875)
  line L1 (65.405, -1.5875) -> (133.35, -1.5875)
  line L2 (133.35, -1.5875) -> (133.35, 4.7625)
  line L3 (133.35, 4.7625) -> (-31.75, 4.7625)
  line L4 (-31.75, 4.7625) -> (-31.75, -4.7625)
  line L5 (-31.75, -4.7625) -> (65.405, -4.7625)
  circle A1 centre (117.475, 11.4427) radius 2.1
  circle A2 centre (117.475, 11.4427) radius 3.175
  circle A3 centre (106.045, 11.4427) radius 2.1
  circle A4 centre (106.045, 11.4427) radius 3.175
  line L6 (117.475, 8.2677) -> (106.045, 8.2677)
  line L7 (117.475, 14.6177) -> (106.045, 14.6177)
  line L8 (106.045, 14.6177) -> (70.9402, 14.6177)
  line L9 (70.9402, 14.6177) -> (65.405, 6.5046)
  line L10 (106.045, 8.2677) -> (74.295, 8.2677)
  line L11 (74.295, 8.2677) -> (65.405, -4.7625)
  line L12 (65.405, 6.5046) -> (65.405, -4.7625)
  line L13 (65.405, 6.5046) -> (64.2164, 4.7625)
  line L14 (120.65, 8.2677) -> (102.87, 8.2677)
  line L15 (102.87, 8.2677) -> (102.87, 14.6177)
  line L16 (102.87, 14.6177) -> (120.65, 14.6177)
  line L17 (120.65, 14.6177) -> (120.65, 8.2677)
  dimension "d38" = 4.2
  dimension "d39" = 9.8552
  dimension "d40" = 6.35
  dimension "d45" = 4.2
  dimension "d46" = 6.35
  dimension "d47" = 11.43
  dimension "d66" = 6.35
  dimension "d68" = 31.75
  dimension "d69" = 6.35
  constraint vertical A0.centre A1.centre
  constraint concentric A1 A2
  constraint concentric A3 A4
  constraint horizontal A1.centre A3.centre
  constraint coincident A2 L6.start
  constraint coincident A4 L6.end
  constraint coincident A2 L7.start
  constraint coincident A4 L7.end
  constraint tangent A4 L7
  constraint horizontal L6
  constraint horizontal L7
  constraint parallel L7 L8
  constraint parallel L3 L10
  constraint coincident L0.start L5.end
  constraint parallel L9 L11
  constraint vertical L9.end L0.start
  constraint coincident L3 L13.end
  constraint parallel L9 L13
  constraint horizontal L14
  constraint vertical L15
  constraint horizontal L16
  constraint vertical L17
  constraint coincident L8 L15.end
  constraint coincident L10 L14.end
  constraint tangent A2 L17
  constraint tangent A4 L15
  measures "d38" diameter of A1
  measures "d39" vertical distance of A0.centre A1.centre
  measures "d40" diameter of A2
  measures "d45" diameter of A3
  measures "d46" diameter of A4
  measures "d47" distance of A1.centre A3.centre
  measures "d66" distance of L8 L10
  measures "d68" distance of L6.end L10.end
  measures "d69" distance of L9 L11
extrude "Extrude7" cut sketch "Sketch8" against normal blind 6.35 contours L0 L1 L11 L12 | L1 L2 L3 L11
extrude "Extrude8" add sketch "Sketch8" along normal blind -6.35 and the other way blind 2.54 contours L0 L1 L11 L12 | L1 L3 L11 L12 | L3 L8 L9 L10 L11 L12 L15 | L3 L12 L13 | A4 L10 L14 L15 | A4 L8 L15 L16 | A4 | A2 A4 L6 L7 L14 L16 | A2 | A2 L14 L17 | A2 L16 L17 | A1 | A3
extrude "Extrude9" add sketch "Sketch8" against normal blind 2.54 contours L0 L1 L11 L12 | A4 L10 L14 L15 | A4 L8 L15 L16 | A4 | A2 A4 L6 L7 L14 L16 | A2 | A2 L14 L17 | A2 L16 L17 | A1 | A3
sketch "Sketch10" plane through (0, 0, -4.7625) normal (0, 0, -1) x (1, 0, 0)
  line L0 (6.35, 65.405) -> (0, 65.405)
  line L1 (0, 65.405) -> (0, -31.75)
  line L2 (0, -31.75) -> (6.35, -31.75)
  line L3 (6.35, -31.75) -> (6.35, 65.405)
  line L4 (6.35, -31.75) -> (0, -31.75)
  line L5 (0, -31.75) -> (0, 65.405)
  line L6 (0, 65.405) -> (6.35, 65.405)
  line L7 (6.35, 65.405) -> (6.35, -31.75)
  constraint horizontal L4
  constraint vertical L5
  constraint horizontal L6
  constraint vertical L7
  constraint coincident L0.end L1.start
  constraint coincident L2.end L3.start
extrude "Extrude12" add sketch "Sketch10" along normal blind 0.4318
sketch "Sketch11" plane through (0, 31.75, 0) normal (0, 1, 0) x (-1, 0, 0)
  line L0 (0, -5.1943) -> (0, 4.7625)
  line L1 (0, 4.7625) -> (-6.35, 4.7625)
  line L2 (-6.35, 4.7625) -> (-6.35, -5.1943)
  line L3 (-6.35, -5.1943) -> (0, -5.1943)
  line L4 (0, -5.1943) -> (-6.35, -5.1943)
  line L5 (-6.35, -5.1943) -> (-6.35, 4.7625)
  line L6 (-6.35, 4.7625) -> (0, 4.7625)
  line L7 (0, 4.7625) -> (0, -5.1943)
  constraint horizontal L4
  constraint vertical L5
  constraint horizontal L6
  constraint vertical L7
  constraint coincident L1.end L2.start
  constraint coincident L0.start L3.end
extrude "Extrude13" add sketch "Sketch11" along normal blind 12.7
sketch "Sketch12" plane through (0, 0, 4.7625) normal (0, 0, 1) x (-1, 0, 0)
  line L0 (-2.54, 64.2164) -> (-6.35, 64.2164)
  line L1 (-6.35, 64.2164) -> (-6.35, -44.45)
  line L2 (-6.35, -44.45) -> (0, -44.45)
  line L3 (0, -44.45) -> (0, 71.9035)
  line L4 (0, 71.9035) -> (-2.54, 71.9035)
  line L5 (-2.54, 71.9035) -> (-2.54, 64.2164)
  line L6 (0, -44.45) -> (-6.35, -44.45)
  line L7 (-6.35, -44.45) -> (-6.35, 6.35)
  line L8 (-6.35, 6.35) -> (0, 6.35)
  line L9 (0, 6.35) -> (0, -44.45)
  dimension "d74" = 50.8
  constraint horizontal L6
  constraint vertical L7
  constraint horizontal L8
  constraint vertical L9
  constraint coincident L1 L7.end
  constraint coincident L2.end L3.start
  measures "d74" distance of L2.end L8.end
extrude "Extrude14" add sketch "Sketch12" along normal blind 6.35 contours L1 L2 L3 L6 L7 L8 L9
sketch "Sketch13" plane through (6.35, 0, 0) normal (1, 0, 0) x (0, 1, 0)
  line L0 (-6.35, 4.7625) -> (-64.2164, 4.7625)
  line L1 (-64.2164, 4.7625) -> (-70.9402, 14.6177)
  line L2 (-70.9402, 14.6177) -> (-120.65, 14.6177)
  line L3 (-120.65, 14.6177) -> (-120.65, 8.2677)
  line L4 (-120.65, 8.2677) -> (-74.295, 8.2677)
  line L5 (-74.295, 8.2677) -> (-65.405, -4.7625)
  line L6 (-65.405, -4.7625) -> (-65.405, -5.1943)
  line L7 (-65.405, -5.1943) -> (44.45, -5.1943)
  line L8 (44.45, -5.1943) -> (44.45, 11.1125)
  line L9 (44.45, 11.1125) -> (-6.35, 11.1125)
  line L10 (-6.35, 11.1125) -> (-6.35, 4.7625)
  line L11 (44.45, -5.1943) -> (-6.35, -5.1943)
  line L12 (-0.4841, 4.9657) -> (-6.35, -5.1943)
  line L13 (44.45, -5.1943) -> (44.45, 4.9657)
  line L14 (-0.4841, 4.9657) -> (44.45, 4.9657)
  dimension "d77" = 10.16
  dimension "d78" = 50.8
  dimension "d79" = 60
  constraint coincident L7.end L8.start
  constraint coincident L7 L11.end
  constraint coincident L8 L13.end
  constraint horizontal L14
  measures "d77" distance of L7.end L13.end
  measures "d78" distance of L7.end L11.end
  measures "d79" angle of L11 L12
extrude "Extrude15" cut sketch "Sketch13" against normal blind 6.35 contours L7 L8 L11 L12 L13 L14
fillet "Fillet1" radius 19.05 1 edges at (3.175, -6.35, 4.7625)
fillet "Fillet2" radius 6.35 1 edges at (3.175, -0.4841, 4.9657)
sketch "Sketch15" plane through (0, 44.45, 0) normal (0, 1, 0) x (-1, 0, 0)
  line L0 (-6.35, 4.9657) -> (0, 4.9657)
  line L1 (0, 4.9657) -> (0, 11.1125)
  line L2 (0, 11.1125) -> (-6.35, 11.1125)
  line L3 (-6.35, 11.1125) -> (-6.35, 4.9657)
  line L4 (34.925, 34) -> (-41.275, 34)
  line L5 (-41.275, 34) -> (-41.275, -42.2)
  line L6 (-41.275, -42.2) -> (34.925, -42.2)
  line L7 (34.925, -42.2) -> (34.925, 34)
  line L8 (34.925, 34) -> (-41.275, -42.2) construction
  line L9 (-41.275, 34) -> (34.925, -42.2) construction
  point P0 (-3.175, -4.1)
  dimension "d92" = 76.2
  dimension "d93" = 76.2
  dimension "d94" = 9.0657
  dimension "d95" = 34.925
  constraint horizontal L4
  constraint perpendicular L4 L5
  constraint parallel L4 L6
  constraint parallel L5 L7
  constraint coincident L8 P0
  constraint coincident L9 P0
  measures "d92" distance of L5.end L6.end
  measures "d93" distance of L4.end L5.end
  measures "d94" distance of L0 P0
  measures "d95" distance of L1 L7
extrude "Extrude19" cut sketch "Sketch15" against normal blind 118.745 contours L0 L1 L2 L3 | L4 L5 L6 L7
extrude "Extrude20" cut 1 faces at (3.81, -74.295, 10.3844) along direction (0, -1, 0) blind 12.7
extrude "Extrude16" [suppressed]
extrude "Extrude17" [suppressed]
sketch "Sketch14" plane through (6.35, 0, 0) normal (1, 0, 0) x (0, 1, 0)
  line L0 (-6.35, -5.1943) -> (-2.3172, 1.7907)
  arc A0 (3.1821, 4.9657) -> (-2.3172, 1.7907) centre (3.1821, -1.3843) ccw
  line L1 (3.1821, 4.9657) -> (44.45, 4.9657)
  line L2 (44.45, 4.9657) -> (44.45, 11.1125)
  line L3 (44.45, 11.1125) -> (-6.35, 11.1125)
  arc A1 (-20.549, 4.7625) -> (-6.35, 11.1125) centre (-20.549, 23.8125) ccw
  line L4 (-20.549, 4.7625) -> (-64.2164, 4.7625)
  line L5 (-64.2164, 4.7625) -> (-70.9402, 14.6177)
  line L6 (-70.9402, 14.6177) -> (-120.65, 14.6177)
  line L7 (-120.65, 14.6177) -> (-120.65, 8.2677)
  line L8 (-120.65, 8.2677) -> (-74.295, 8.2677)
  line L9 (-74.295, 8.2677) -> (-65.405, -4.7625)
  line L10 (-65.405, -4.7625) -> (-65.405, -5.1943)
  line L11 (-65.405, -5.1943) -> (-6.35, -5.1943)
  line L12 (-74.295, 8.2677) -> (-74.295, 14.6177)
  constraint coincident L8.end L9.start
  constraint coincident L6 L12.end
  constraint perpendicular L6 L12
extrude "Extrude18" [suppressed]
sketch "Sketch9" plane through (6.35, 0, 0) normal (1, 0, 0) x (0, 1, 0)
  line L0 (31.75, -5.1943) -> (31.75, 4.7625)
  line L1 (31.75, 4.7625) -> (-64.2164, 4.7625)
  line L2 (17.4625, -1.5875) -> (17.4625, -4.7625)
  line L3 (17.4625, -4.7625) -> (7.9375, -4.7625)
  line L4 (7.9375, -4.7625) -> (7.9375, -1.5875)
  line L5 (7.9375, -1.5875) -> (17.4625, -1.5875)
  line L6 (0, -2.1971) -> (7.9375, -2.1971)
  line L7 (-64.2164, 4.7625) -> (-70.9402, 14.6177)
  line L8 (-70.9402, 14.6177) -> (-120.65, 14.6177)
  line L9 (-120.65, 14.6177) -> (-120.65, 8.2677)
  line L10 (-120.65, 8.2677) -> (-74.295, 8.2677)
  line L11 (-74.295, 8.2677) -> (-65.405, -4.7625)
  line L12 (-65.405, -4.7625) -> (-65.405, -5.1943)
  line L13 (-65.405, -5.1943) -> (31.75, -5.1943)
  dimension "d55" = 9.525
  dimension "d56" = 3.175
  dimension "d57" = 7.9375
  constraint vertical L2
  constraint horizontal L3
  constraint vertical L4
  constraint perpendicular L2 L5
  constraint coincident L4 L6.end
  constraint perpendicular L4 L6
  measures "d55" distance of L4.end L2.start
  measures "d56" distance of L2.end L2.start
  measures "d57" distance of L6.start L6.end
extrude "Extrude10" [suppressed]
extrude "Extrude11" [suppressed]
equation "d7 = 0.5 in - ( 0.2 / 2 ) * 1 in"
equation "d10 = ( 0.375 / 2 ) * 1 in"
equation "d11 = ( ( 1.5 - 1 ) / 2 ) * 1 in"
equation "d39 = 0.263 in + 0.125 in"

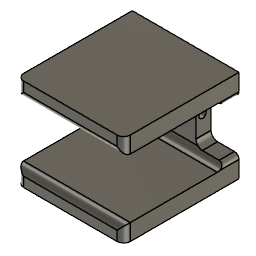
design "Bracket For Yellow Motors"
Autodesk Fusion 360 part; units mm, degrees
sketch "Sketch1" plane through (0, 0, 0) normal (0, 0, 1) x (1, 0, 0)
  line L0 (0, 0) -> (41.148, 0)
  line L1 (41.148, 0) -> (41.148, 44.45)
  line L2 (41.148, 44.45) -> (0, 44.45)
  line L3 (0, 44.45) -> (0, 0)
  dimension "d1" = 41.148
  dimension "d2" = 44.45
  constraint horizontal L0
  constraint vertical L1
  constraint horizontal L2
  constraint vertical L3
  constraint coincident L0.start L3.end
  measures "d1" distance of L0.start L0.end
  measures "d2" distance of L0.start L2.end
extrude "Extrude1" add sketch "Sketch1" along normal blind 6.35